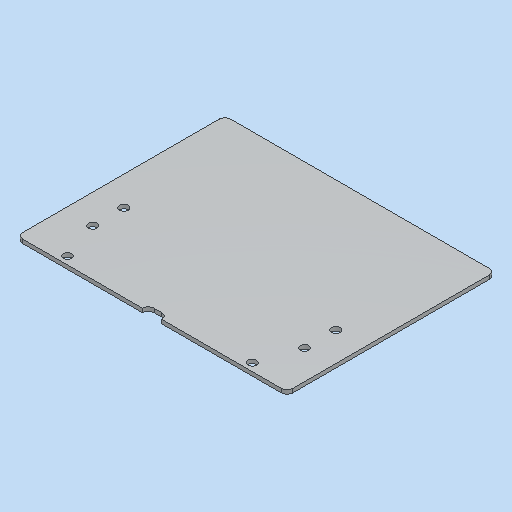
# Autodesk Inventor part: MM0948AN100_G01_154
Saved by Autodesk Inventor 2023.3 (Build 273359000, 359)
## iProperties
RuleStatus: InUse
Created: 2023-04-13
Part Number: MM0948AN100_G01_154
Material: 3.3535 AlMg3 - AW 5754 (Blech)
Description: =<RBPARTNOTITLE2>
Document SubType Name: Blech
Designer: ric7an
Mass: 79.5866 g
Surface Area: 306.376 cm^2
Volume: 29.4874 cm^3
Density: 2.699 g/cm^3
Sheet Metal Rule: Standard_mm
Appearance: Aluminium AnP
AnP_Kategorie: 1
AnP_Material: =<Material>
MaxAbmaße: 2 x 107 x 139 (FM)
AnP_TemplVers: 20200821
RBDOCUMENTTYPE: DRF
RBDOCUMENTVERSION: 00
RBDRAWINGMAINSCALE: 1:1
RBDRAWINGMISSINGSPEC: --
RBDRAWINGVOLUME: --
RBDSV1: 0850
RBGBEDGESIN1: +0,5
RBGBEDGESIN2: +0,2
RBGBEDGESOUT1: -0,3
RBGBEDGESOUT2: -0,1
RBMATERIAL: =<Material>
RBMATMEETS: --
RBMATNO: =<Part Number>
RBPARTMADEOF: 2 x 107 x 139 (FM)
RBPARTNO: SIEHE MNR
RBPARTNOTITLE1: manufactured part
RBPARTNOTITLE2: Anfertigungsteil
RBPARTSAFETYINDICATOR: --
RBSURFACE: --
RBSURFACE2: eloxiert E6/EV1 aluminiumfarbig
RBZEDGESNORM: ISO13715:2002-06
RBZGENDIMCLASS: m
RBZGENDIMNORM: ISO 2768-1:1989-11
RBZGENGEOCLASS: H
RBZGENGEONORM: ISO 2768-2:1989-11
RBZSURFACENORM: ISO13D2:2002-02
RBZTOLERANCENORM: ISO 14405-1:2010-12
Author: ric7an
Keywords: =<RBPARTMADEOF>
Comments: =<RBSURFACE2>
Revision Number: 01
Autodesk Inventor part; units mm, degrees
ref_plane "YZ Plane" through (0, 0, 0) normal (1, 0, 0) x (0, 1, 0)
ref_plane "XZ Plane" through (0, 0, 0) normal (0, 1, 0) x (-1, 0, 0)
ref_plane "XY Plane" through (0, 0, 0) normal (0, 0, 1) x (1, 0, 0)
sketch "Skizze1" plane through (0, 0, 0) normal (0, 0, 1) x (1, 0, 0)
  line L0 (-69.5, 107) -> (69.5, 107)
  line L1 (69.5, 107) -> (69.5, 0)
  line L2 (69.5, 0) -> (-69.5, 0)
  line L3 (-69.5, 0) -> (-69.5, 107)
  line L4 (0, 128.4) -> (0, -21.4)
  line L5 (-97.3, 0) -> (97.3, 0)
  point P0 (0, 0)
  dimension "d0" = 139
  dimension "d1" = 107
  measures "d0" distance of L0.start L0.end
  measures "d1" distance of L0.end L1.end
extrude "Grobblech1" add sketch "Skizze1" along normal blind 2
sketch "Skizze2" plane through (0, 0, 2) normal (0, 0, 1) x (1, 0, 0)
  line L0 (0, 128.4) -> (0, -21.4) projected
  line L1 (69.5, 0) -> (-69.5, 0) projected
  point P0 (0, 0)
  point P1 (-47.5, 4)
  point P2 (47.5, 4)
  dimension "d3" = 4
  dimension "d4" = 95
  constraints: 1 symmetric about line
  measures "d3" distance from line of L1 point (47.5, 4)
  measures "d4" distance of point (47.5, 4) point (-47.5, 4)
hole "Bohrung1" at (-47.5, 4, 2) at (47.5, 4, 2) direction (0, 0, -1) diameter 4.5 end through all clearance for "Inbusschraube ISO 4762  versenkt" size "M4" standard "ISO"
fillet "Eckenrundung1" radius 3 4 edges at (-69.5, 0, 1) (69.5, 0, 1) (69.5, 107, 1) (-69.5, 107, 1)
sketch "Skizze3" plane through (0, 0, 2) normal (0, 0, 1) x (1, 0, 0)
  line L0 (66.5, 0) -> (-66.5, 0) projected
  line L1 (0, 128.4) -> (0, -21.4) projected
  point P0 (0, 0)
  point P1 (54.5, 40)
  point P2 (54.5, 24)
  point P3 (-54.5, 40)
  point P4 (-54.5, 24)
  dimension "d13" = 16
  dimension "d14" = 24
  dimension "d15" = 109
  constraints: 2 horizontal alignment, 2 vertical alignment, 1 symmetric about line
  measures "d13" distance of point (54.5, 40) point (54.5, 24)
  measures "d14" distance from line of L0 point (54.5, 24)
  measures "d15" distance of point (54.5, 40) point (-54.5, 40)
hole "Bohrung2" at (54.5, 40, 2) at (54.5, 24, 2) at (-54.5, 40, 2) at (-54.5, 24, 2) direction (0, 0, -1) diameter 4.5 end through all clearance for "Inbusschraube ISO 4762  versenkt" size "M4" standard "ISO"
sketch "Skizze4" plane through (0, 0, 2) normal (0, 0, 1) x (1, 0, 0)
  line L0 (66.5, 0) -> (-66.5, 0) projected
  line L1 (-5, 0) -> (5, 0)
  line L2 (5, 0) -> (5, 3)
  line L3 (5, 3) -> (-5, 3)
  line L4 (-5, 3) -> (-5, 0)
  line L5 (0, 128.4) -> (0, -21.4) projected
  point P0 (0, 0)
  dimension "d23" = 3
  dimension "d24" = 10
  constraints: 8 end point, 2 parallel, 1 horizontal, 1 perpendicular, 1 point on line, 1 other
  measures "d23" distance of L1.end L2.end
  measures "d24" distance of L2.end L3.end
extrude "Ausschneiden1" cut sketch "Skizze4" against normal blind 2
fillet "Eckenrundung2" radius 3 2 edges at (-5, 3, 1) (5, 3, 1)
equation "\"d10\" = Stärke"
equation "\"d21\" = Stärke"
equation "\"d25\" = Stärke"
equation "\"d2\" = Stärke"
equation "\"Biegeradius\" = Stärke"
equation "\"BreiteBiegungsfreistellung\" = Stärke"
equation "\"TiefeBiegungsfreistellung\" = 0.5 * Stärke"
equation "\"GrößeEckenfreistellung\" = 4 * Stärke"
equation "\"MinimalRest\" = 2 * Stärke"
equation "\"Übergangsradius\" = Biegeradius"
equation "\"JacobiRadiusGröße\" = Biegeradius"
equation "\"Abstandsgröße\" = Stärke"
equation "\"Stärke\" = 2"
